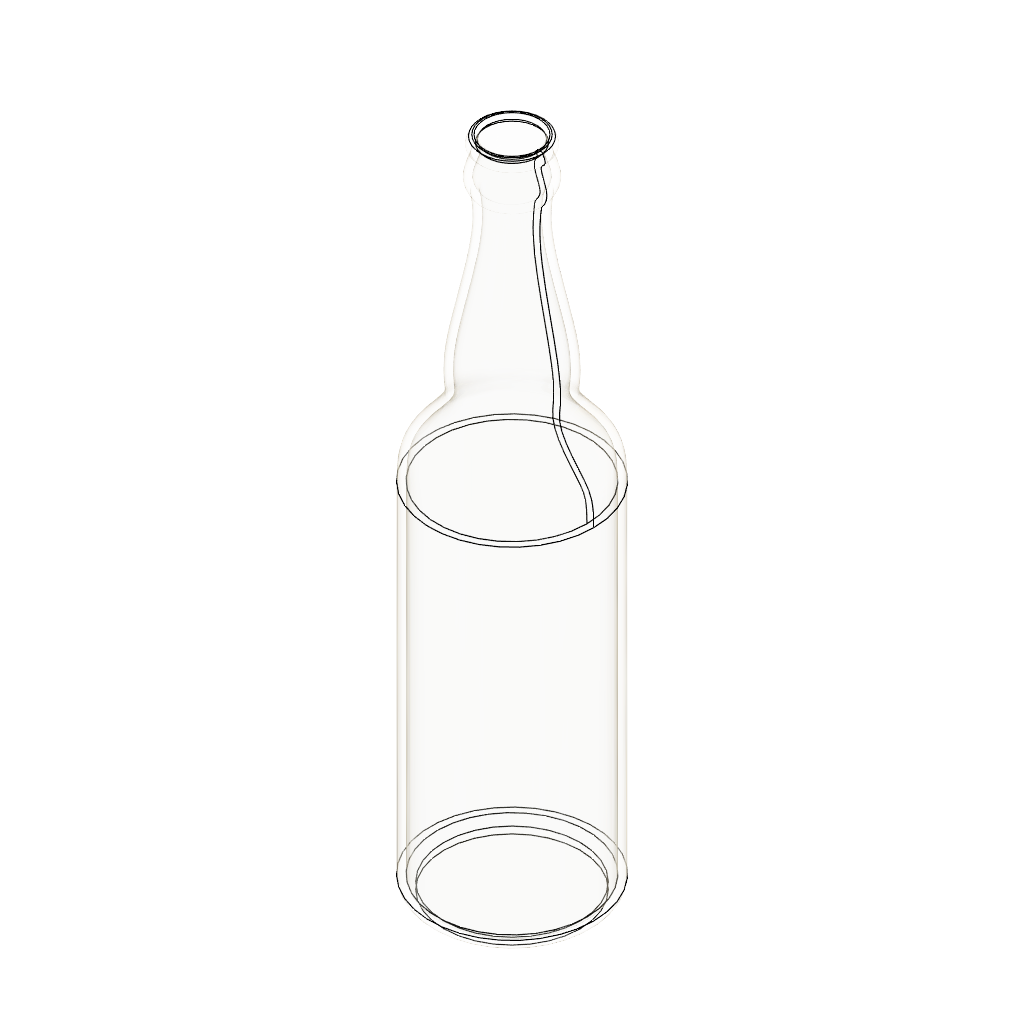
Glass-Soda-Bottle (Autodesk Fusion 360 design; units mm, degrees)
part number: 2026-11-10-10-36-03-849
Autodesk Fusion 360 part; units mm, degrees
sketch "Sketch1" plane through (0, 0, 0) normal (0, 1, 0) x (1, 0, 0)
  line L0 (0, 0) -> (0, -240)
  line L1 (0, 0) -> (30, 0)
  line L2 (30, 0) -> (30, -130)
  spline S0 degree 5 poles (30, -130) (30, -130.8262) (29.9825, -132.3903) (29.904, -134.4717) (29.6866, -136.7482) (29.1862, -138.9448) (28.4133, -140.7328) (27.3399, -142.3624) (25.971, -144.0479) (24.3656, -145.9158) (22.6481, -147.9702) (20.975, -150.1404) (19.5073, -152.3171) (18.3805, -154.3944) (17.6778, -156.3055) (17.3951, -158.0699) (17.4319, -159.8081) (17.6353, -161.6917) (17.8337, -163.9056) (17.8721, -166.6092) (17.6531, -169.8896) (17.1454, -173.7534) (16.3666, -178.1467) (15.3742, -182.9664) (14.2528, -188.0754) (13.1035, -193.315) (12.0331, -198.5213) (11.1403, -203.5315) (10.5109, -208.2153) (10.1915, -212.4465) (10.2139, -216.2176) (10.4793, -219.3629) (10.7477, -221.4738) (10.9008, -222.4392) (10.8859, -222.3784) (11.3012, -222.7084) (12.2125, -224.1262) (12.9097, -225.948) (12.8724, -227.877) (12.197, -230.0919) (11.2854, -232.2528) (10.633, -234.0442) (10.6137, -235.1973) (11.2176, -235.7692) (11.9648, -236.1842) (12.344, -236.8853) (12.1553, -237.8456) (11.6996, -238.823) (11.2564, -239.5886) (11, -240) knots 0 0 0 0 0 0 0.022222 0.044444 0.066667 0.088889 0.111111 0.133333 0.155556 0.177778 0.2 0.222222 0.244444 0.266667 0.288889 0.311111 0.333333 0.355556 0.377778 0.4 0.422222 0.444444 0.466667 0.488889 0.511111 0.533333 0.555556 0.577778 0.6 0.622222 0.644444 0.666667 0.688889 0.711111 0.733333 0.755556 0.777778 0.8 0.822222 0.844444 0.866667 0.888889 0.911111 0.933333 0.955556 0.977778 1 1 1 1 1 1
  line L3 (9.7447, -221.2084) -> (12.1989, -223.6977)
  line L4 (11.1796, -213.2634) -> (14.3509, -239.1646)
  line L5 (10.7445, -199.8739) -> (9.8062, -224.8129)
  line L6 (30, -110.6384) -> (30, -149.3616)
  line L7 (0, -240) -> (11, -240)
  point P0 (26.1767, -143.7722)
  point P1 (17.9711, -155.6454)
  point P2 (17.8248, -165.1127)
  point P3 (10.2754, -212.3434)
  point P4 (10.9718, -222.453)
  point P5 (12.7653, -226.214)
  point P6 (10.7114, -234.7848)
  point P7 (11.8179, -236.1942)
  dimension "d1" = 240
  dimension "d2" = 30
  dimension "d3" = 130
  dimension "d4" = 11
  constraint coincident L0.start L1.start
  constraint vertical L0
  constraint perpendicular L0 L1
  constraint perpendicular L1 L2
  constraint midpoint P4 L3
  constraint midpoint P5 L4
  constraint midpoint P3 L5
  constraint midpoint L2.end L6
  constraint vertical L6
  constraint perpendicular L0 L7
  constraint coincident S0.end L7.end
  measures "d1" distance of L0.start L0.end
  measures "d2" distance of L0.start L1.end
  measures "d3" distance of L1.end L2.end
  measures "d4" distance of L0.end S0.end
revolve "Revolve1" add sketch "Sketch1" angle 360 about axis through (0, 0, 0) along (0, 0, 1)
fillet "Fillet1" radius 5 1 edges at (-27.9698, -10.8485, 0)
shell "Shell1" thickness 2.5 removed faces 1 at (-0.8159, -0.3929, 240)
fillet "Fillet2" radius 1 2 edges at (-10.2556, -3.9778, 240) (-8.054, 0.0033, 240)
